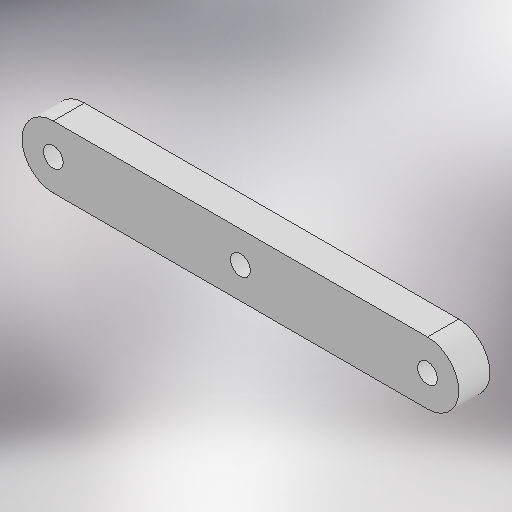
# Autodesk Inventor part: 3D_link2
Saved by Autodesk Inventor 2025.3 (Build 293356030, 356C)
## iProperties
Created: 2026-05-21
Part Number: 3D_link2
Material: 一般
Document SubType Name: Modeling
Designer: ibuki_ono
Density: 1 g/cm^3
Appearance: 既定
Author: ibuki_ono
Autodesk Inventor part; units mm, degrees
ref_plane "YZ Plane" through (0, 0, 0) normal (1, 0, 0) x (0, 1, 0)
ref_plane "XZ Plane" through (0, 0, 0) normal (0, 1, 0) x (-1, 0, 0)
ref_plane "XY Plane" through (0, 0, 0) normal (0, 0, 1) x (1, 0, 0)
sketch "スケッチ1" plane through (0, 0, 0) normal (0, 0, 1) x (1, 0, 0)
  line L0 (-30, 0) -> (30, 0) construction
  line L1 (-30, -5) -> (30, -5)
  line L2 (30, 5) -> (-30, 5)
  arc A0 (-30, 5) -> (-30, -5) centre (-30, 0) ccw
  arc A1 (30, -5) -> (30, 5) centre (30, 0) ccw
  line L3 (0, 0) -> (60, 0) construction
  dimension "d0" = 30
  dimension "d1" = 0
  dimension "d2" = 10
  constraints: 10 end point, 4 point on circle, 4 tangent, 2 centre point, 2 horizontal, 1 collinear, 1 midpoint, 1 parallel
  measures "d0" distance of L3.start L0.end
  measures "d1" distance between parallel lines of L0 L3
  measures "d2" diameter of A1
extrude "押し出し1" add sketch "スケッチ1" along normal mid plane 5
sketch "スケッチ2" plane through (0, 0, 2.5) normal (0, 0, 1) x (1, 0, 0)
  arc A0 (-30, 5) -> (-30, -5) centre (-30, 0) ccw projected
  arc A1 (30, -5) -> (30, 5) centre (30, 0) ccw projected
  point P0 (0, 0)
hole "穴1" at (-30, 0, 2.5) at (30, 0, 2.5) at (0, 0, 2.5) direction (0, 0, -1) diameter 3.2 end through all
